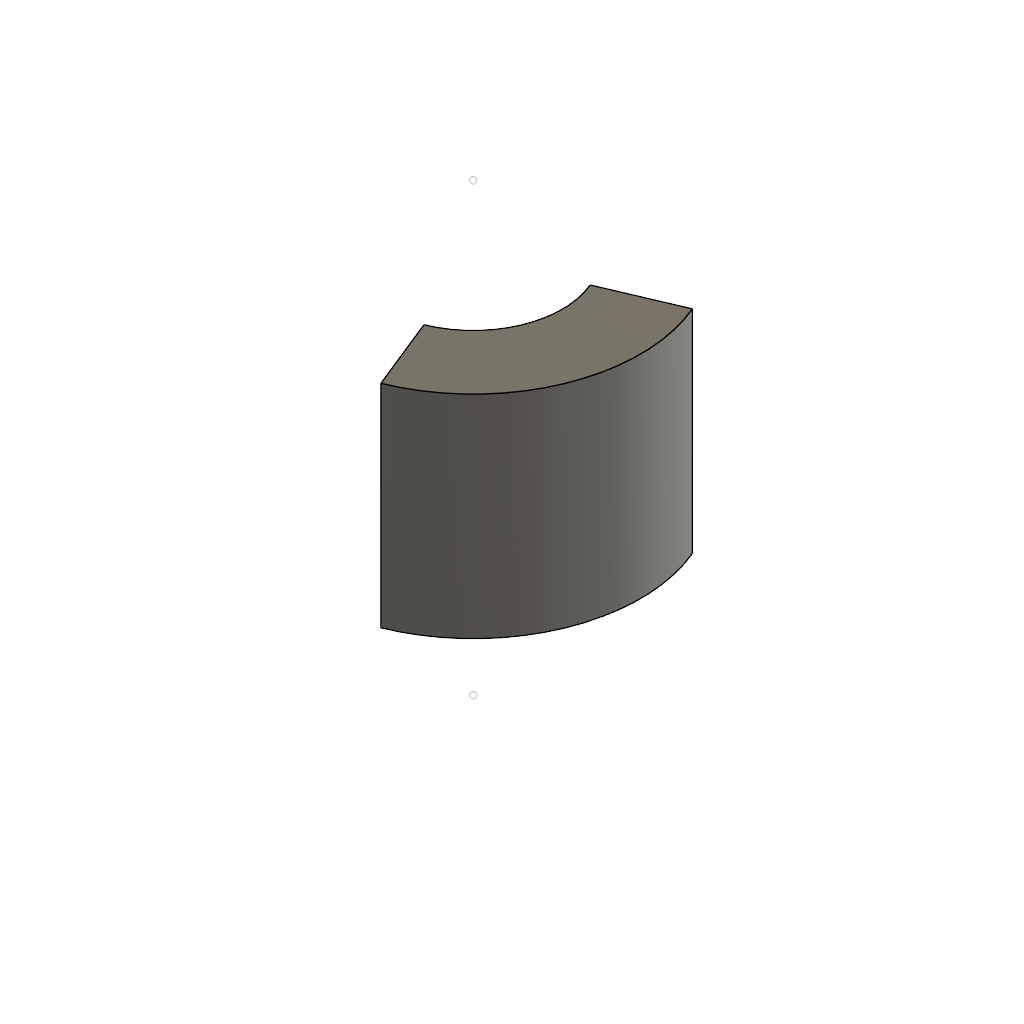
reversed_edit_first (Autodesk Fusion 360 design; units mm, degrees)
part number: 2026-11-27-16-03-33-157
Autodesk Fusion 360 part; units mm, degrees
sketch "AxisSupport" plane through (0, 0, 0) normal (0, 0, 1) x (1, 0, 0)
  point P0 (11, -7)
  point P1 (11, -47)
sketch "RevolveProfile" plane through (0, 0, 0) normal (0, 0, 1) x (1, 0, 0)
  line L0 (19, -13) -> (19, -32)
  line L1 (19, -32) -> (26, -32)
  line L2 (26, -32) -> (26, -13)
  line L3 (26, -13) -> (19, -13)
revolve "UnequalRevolve" add sketch "RevolveProfile" angle 68 about axis through (11, 1, 0) along (0, -1, 0) second angle 23
